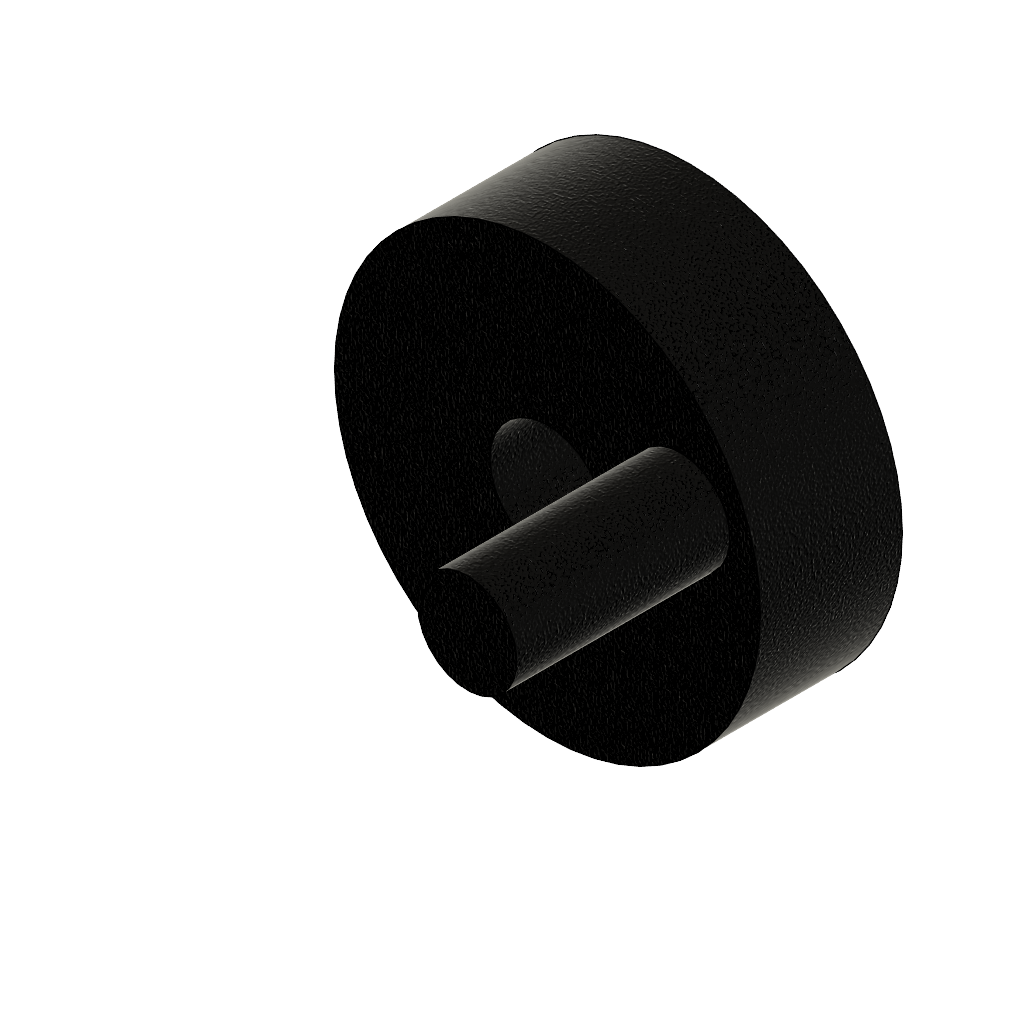
Crank-Rocker_final (Autodesk Fusion 360 archive; units mm, degrees)
design "Handle"
Autodesk Fusion 360 part; units mm, degrees
sketch "Sketch1" plane through (0, 0, 0) normal (0, 0, 1) x (1, 0, 0)
  circle A0 centre (0, 0) radius 15
  dimension "d1" = 30
  constraint coincident A0.centre origin
  measures "d1" diameter of A0
extrude "Extrude1" add sketch "Sketch1" along normal blind 10
sketch "Sketch2" plane through (0, 0, 0) normal (0, 0, 1) x (1, 0, 0)
  circle A0 centre (0, 0) radius 2
  circle A1 centre (9.2693, 3.7524) radius 3.5
  dimension "d4" = 4
  dimension "d6" = 7
  constraint coincident A0.centre origin
  measures "d4" diameter of A0
  measures "d6" diameter of A1
extrude "Extrude2" cut sketch "Sketch2" along normal blind 10 contours A0
sketch "Sketch3" plane through (0, 0, 10) normal (0, 0, 1) x (1, 0, 0)
  circle A0 centre (0, 0) radius 2
  circle A1 centre (0, 0) radius 15
  circle A2 centre (9.3486, 3.5501) radius 3.5
  dimension "d10" = 7
  measures "d10" diameter of A2
extrude "Extrude3" add sketch "Sketch3" along normal blind 15 contours A2
sketch "Sketch4" plane through (0, 0, 10) normal (0, 0, 1) x (1, 0, 0)
  circle A0 centre (9.3486, 3.5501) radius 3.5
  circle A1 centre (0, 0) radius 2
  circle A2 centre (0, 0) radius 15
  circle A3 centre (0, 0) radius 4.05
  dimension "d13" = 8.1
  constraint coincident A1.centre A2.centre
  measures "d13" diameter of A3
extrude "Extrude4" cut sketch "Sketch4" against normal blind 10 contours A3

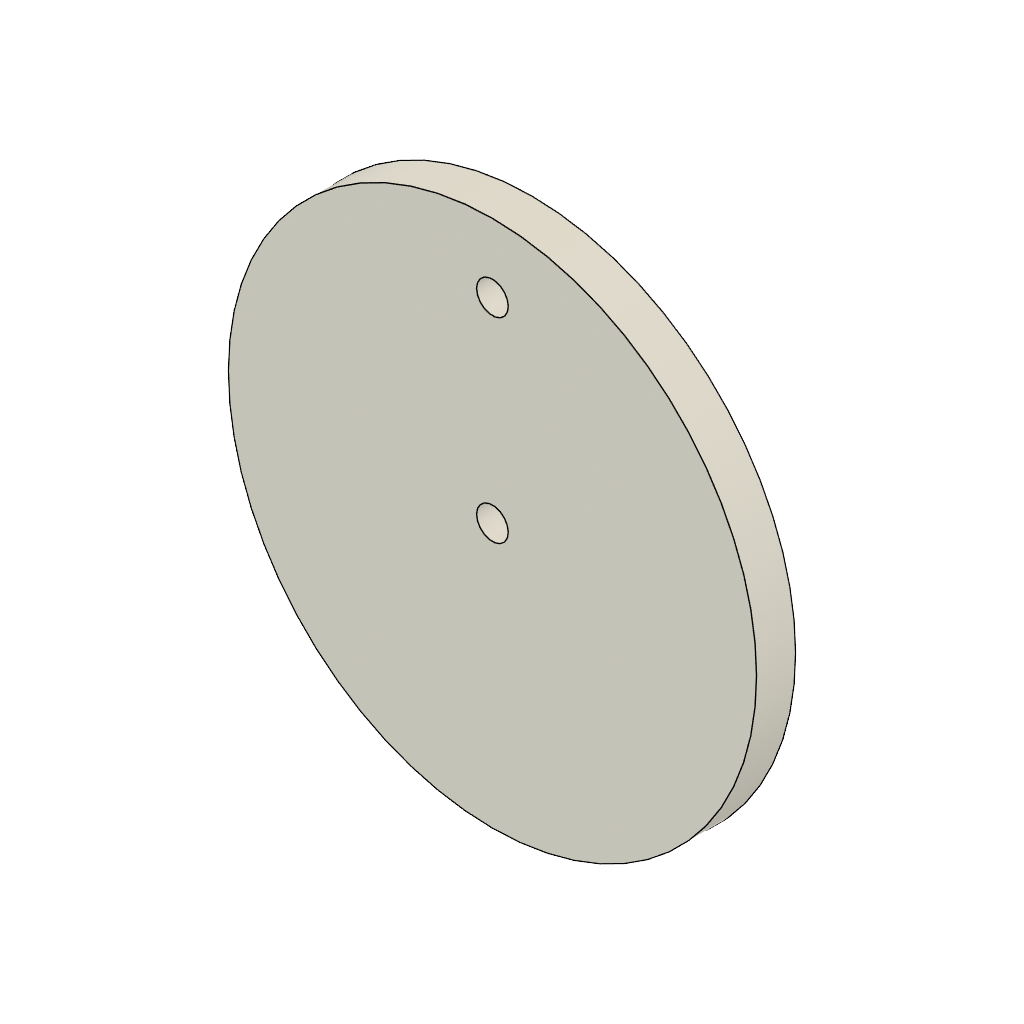
design "Link 4 final"
part number: 2026-11-07-23-02-50-347
Autodesk Fusion 360 part; units mm, degrees
sketch "Sketch1" plane through (0, 0, 0) normal (0, 0, 1) x (1, 0, 0)
  circle A0 centre (0, 0) radius 67.5
  circle A1 centre (0, 0) radius 4.05
  line L0 (0, 0) -> (0, 50)
  circle A2 centre (0, 50) radius 4.05
  dimension "d1" = 135
  dimension "d2" = 8.1
  dimension "d3" = 50
  dimension "d4" = 8.1
  constraint coincident A0.centre A1.centre
  constraint concentric A0 A1
  constraint vertical L0
  constraint coincident L0.end A2.centre
  measures "d1" diameter of A0
  measures "d2" diameter of A1
  measures "d3" distance of A0.centre L0.end
  measures "d4" diameter of A2
extrude "Extrude1" add sketch "Sketch1" along normal blind 5
extrude "Extrude2" add 1 faces at (18.5342, 31.9706, 5) along direction (0, 0, 1) blind 5
equation "d1 = 120 mm + 7.5 mm + 7.5 mm"

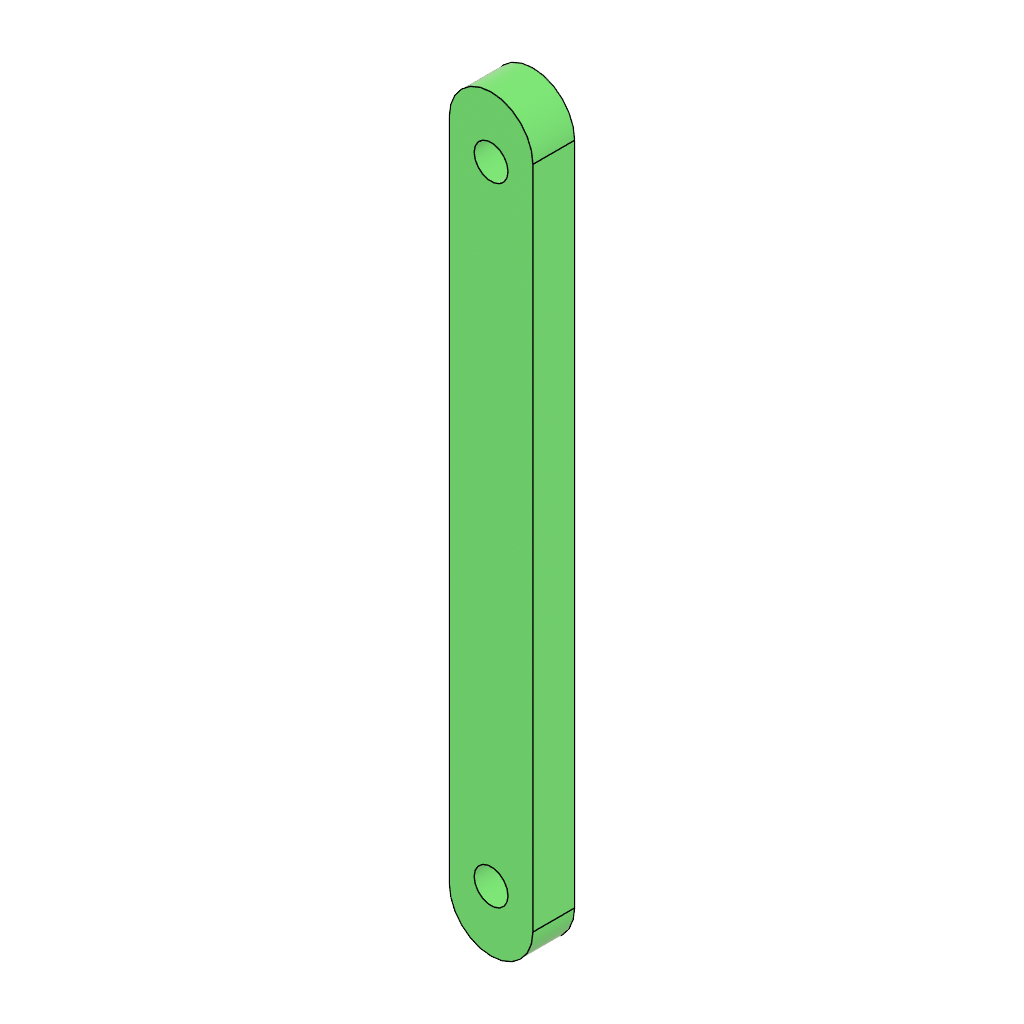
design "Link 3"
Autodesk Fusion 360 part; units mm, degrees
sketch "Sketch1" plane through (0, 0, 0) normal (0, 0, 1) x (1, 0, 0)
  line L0 (0, 0) -> (10, 0)
  line L1 (10, 0) -> (10, 164)
  line L2 (10, 164) -> (0, 164)
  line L3 (0, 164) -> (0, 0)
  dimension "d1" = 10
  dimension "d2" = 164
  constraint horizontal L0
  constraint vertical L1
  constraint horizontal L2
  constraint vertical L3
  constraint coincident L0.start L3.end
  measures "d1" distance of L0.start L0.end
  measures "d2" distance of L0.start L2.end
extrude "Extrude1" add sketch "Sketch1" along normal blind 5
sketch "Sketch2" plane through (0, 0, 5) normal (0, 0, 1) x (1, 0, 0)
  line L0 (0, 164) -> (0, 0)
  line L1 (0, 0) -> (10, 0)
  line L2 (10, 0) -> (10, 164)
  line L3 (10, 164) -> (0, 164)
  circle A0 centre (5, 7) radius 2
  circle A1 centre (5, 157) radius 2
  dimension "d7" = 4
  dimension "d9" = 4
  measures "d7" diameter of A0
  measures "d9" diameter of A1
extrude "Extrude2" cut sketch "Sketch2" against normal blind 10 contours A0 | A1
extrude "Extrude3" add 1 faces at (6.6667, 164, 1.6667) along direction (0, 1, 0) blind 7.5
extrude "Extrude4" add 1 faces at (10, 114.3333, 1.6667) along direction (1, 0, 0) blind 5
extrude "Extrude5" add 1 faces at (0, 114.3333, 1.6667) along direction (-1, 0, 0) blind 5
extrude "Extrude6" add 1 faces at (1.6667, 0, 3.3333) along direction (0, -1, 0) blind 7.5
sketch "Sketch3" plane through (0, 0, 5) normal (0, 0, 1) x (1, 0, 0)
  circle A0 centre (5, 157) radius 2
  circle A1 centre (5, 7) radius 2
  line L0 (15, -7.5) -> (15, 171.5)
  line L1 (15, 171.5) -> (-5, 171.5)
  line L2 (-5, 171.5) -> (-5, -7.5)
  line L3 (-5, -7.5) -> (15, -7.5)
  circle A2 centre (5, 7) radius 4.05
  circle A3 centre (5, 157) radius 4.05
  dimension "d22" = 8.1
  dimension "d23" = 8.1
  constraint concentric A1 A2
  constraint concentric A0 A3
  measures "d22" diameter of A2
  measures "d23" diameter of A3
extrude "Extrude7" cut sketch "Sketch3" against normal blind 20 contours A0 | A2 | A3
fillet "Fillet2" radius 10 4 edges at (15, 171.5, 2.5) (-5, 171.5, 2.5) (15, -7.5, 2.5) (-5, -7.5, 2.5)
extrude "Extrude8" add 1 faces at (-2.6563, 57.9182, 5) along direction (0, 0, 1) blind 5
fillet "Fillet1" [rolled back] radius 5
equation "d2 = 14 mm + 150 mm"
